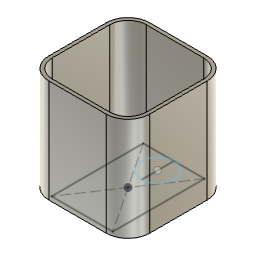
ESP32_S3_CAM_OV3660 v1 (Autodesk Fusion 360 design; units mm, degrees)
Autodesk Fusion 360 part; units mm, degrees
sketch "草图1" plane through (0, 0, 0) normal (0, 0, 1) x (1, 0, 0)
  line L0 (-12, 20) -> (12, 20)
  line L1 (20, 12) -> (20, -12)
  line L2 (12, -20) -> (-12, -20)
  line L3 (-20, -12) -> (-20, 12)
  line L4 (-20, 20) -> (20, -20) construction
  line L5 (20, 20) -> (-20, -20) construction
  arc A0 (-12, 20) -> (-20, 12) centre (-12, 12) ccw
  arc A1 (20, 12) -> (12, 20) centre (12, 12) ccw
  arc A2 (-20, -12) -> (-12, -20) centre (-12, -12) ccw
  arc A3 (12, -20) -> (20, -12) centre (12, -12) ccw
  arc A4 (12, -18.5) -> (18.5, -12) centre (12, -12) ccw
  line L6 (18.5, 12) -> (18.5, -12)
  arc A5 (18.5, 12) -> (12, 18.5) centre (12, 12) ccw
  line L7 (-12, 18.5) -> (12, 18.5)
  arc A6 (-12, 18.5) -> (-18.5, 12) centre (-12, 12) ccw
  line L8 (-18.5, -12) -> (-18.5, 12)
  arc A7 (-18.5, -12) -> (-12, -18.5) centre (-12, -12) ccw
  line L9 (12, -18.5) -> (-12, -18.5)
  line L10 (-10, 20) -> (10, 20)
  line L11 (10, 20) -> (10, -20)
  line L12 (10, -20) -> (-10, -20)
  line L13 (-10, -20) -> (-10, 20)
  line L14 (-10, 20) -> (10, -20) construction
  line L15 (10, 20) -> (-10, -20) construction
  line L16 (20, 0) -> (2.5, 0)
  line L17 (0, 2.5) -> (0, 20)
  arc A8 (-18.1617, -17.1022) -> (-17.1022, -18.1617) centre (-17.6569, -17.6569) ccw
  arc A9 (-17.1022, 18.1617) -> (-18.1617, 17.1022) centre (-17.6569, 17.6569) ccw
  arc A10 (18.1617, 17.1022) -> (17.1022, 18.1617) centre (17.6569, 17.6569) ccw
  arc A11 (17.1022, -18.1617) -> (18.1617, -17.1022) centre (17.6569, -17.6569) ccw
  dimension "d1" = 40
  dimension "d2" = 40
  dimension "d3" = 8
  dimension "d4" = 1.5
  dimension "d29" = 20
  dimension "d30" = 40
  dimension "d63" = 1.5
  constraint horizontal L0
  constraint perpendicular L0 L1
  constraint parallel L0 L2
  constraint parallel L1 L3
  constraint coincident L4 origin
  constraint coincident L5 origin
  constraint coincident L4.start L3
  constraint coincident L4.start L0
  constraint tangent L3 A0
  constraint tangent L0 A0
  constraint coincident L5.start L0
  constraint coincident L5.start L1
  constraint tangent L0 A1
  constraint tangent L1 A1
  constraint equal A0 A1
  constraint coincident L5.end L3
  constraint coincident L5.end L2
  constraint tangent L3 A2
  constraint tangent L2 A2
  constraint equal A0 A2
  constraint coincident L4.end L2
  constraint coincident L4.end L1
  constraint tangent L2 A3
  constraint tangent L1 A3
  constraint equal A0 A3
  constraint horizontal L10
  constraint perpendicular L10 L11
  constraint parallel L10 L12
  constraint parallel L11 L13
  constraint coincident L14 origin
  constraint coincident L15 origin
  constraint midpoint A2 A8.centre
  constraint coincident A2 A8.end
  constraint coincident A2 A8.start
  constraint symmetric L16 A8.end A9.start
  constraint symmetric L16 A8 A9
  constraint symmetric L16 A8.start A9.end
  constraint symmetric L17 A8.end A11.start
  constraint symmetric L17 A8 A11
  constraint symmetric L17 A8.start A11.end
  constraint symmetric L17 A9.end A10.start
  constraint symmetric L17 A9.start A10.end
  constraint symmetric L17 A9 A10
  measures "d1" distance of L4.end L5.end
  measures "d2" distance of L5.start L4.end
  measures "d3" radius of A0
  measures "d29" distance of L11.end L12.end
  measures "d30" distance of L10.end L11.end
  measures "d63" diameter of A8
ref_plane "工作平面1" through (0, 0, 1.5) normal (0, 0, 1) x (1, 0, 0)
sketch "草图3" plane through (0, 0, 1.5) normal (0, 0, 1) x (1, 0, 0)
  line L0 (15, 17) -> (15, -17)
  line L1 (-15, -17) -> (-15, 17)
  line L2 (-15, 23) -> (15, -23) construction
  line L3 (15, 23) -> (-15, -23) construction
  line L4 (13.5, -20.7) -> (13.5, -21.5)
  line L5 (13.5, 17) -> (13.5, -17)
  line L6 (-13.5, -17) -> (-13.5, 17)
  line L7 (-13.5, 20.7) -> (-13.5, 21.5)
  line L8 (15, -17) -> (13.5, -17)
  line L9 (-13.5, -17) -> (-15, -17)
  line L10 (15, 17) -> (13.5, 17)
  line L11 (-13.5, 17) -> (-15, 17)
  dimension "d10" = 30
  constraint parallel L0 L1
  constraint coincident L2 origin
  constraint coincident L3 origin
  constraint perpendicular L1 L10
  constraint perpendicular L1 L8
  constraint coincident L2 L4.start
  constraint coincident L6.start L8
  constraint coincident L6.end L10
  constraint coincident L2 L7.start
  constraint collinear L6 L7
  constraint collinear L8 L9
  constraint collinear L10 L11
  measures "d10" distance of L2.end L3.end
sketch "草图5" plane through (0, 0, 0) normal (0, 1, 0) x (1, 0, 0)
  line L0 (13.5, -40) -> (13.5, -1.5)
  line L1 (-13.5, -1.5) -> (-13.5, -40)
  line L2 (13.5, -40) -> (13.5, -1.5)
  line L3 (13.5, -1.5) -> (-13.5, -1.5)
  line L4 (-13.5, -1.5) -> (-13.5, -40)
  line L5 (13.5, -50) -> (-13.5, -50)
  line L6 (-13.5, -50) -> (-13.5, -1.5)
  line L7 (-13.5, 50) -> (13.5, 50)
  line L8 (13.5, -1.5) -> (13.5, -50)
  dimension "d18" = 38.5
  dimension "d19" = 100
  constraint parallel L0 L1
  constraint vertical L2
  constraint horizontal L3
  constraint vertical L4
  constraint horizontal L5
  constraint perpendicular L5 L6
  constraint parallel L5 L7
  constraint parallel L6 L8
  measures "d18" distance of L1.end L1.start
  measures "d19" distance of L5.end L7.start
sketch "草图6" plane through (0, 0, 0) normal (1, 0, 0) x (0, 1, 0)
  line L0 (-10, 50) -> (10, 50)
  line L1 (10, 50) -> (10, 1.5)
  line L2 (-10, 1.5) -> (-10, 50)
  line L3 (-0.3, 1.5) -> (0, 0) construction
  line L4 (0.3, 1.5) -> (0, 0) construction
  line L5 (-10, 50) -> (10, 50)
  line L6 (10, 50) -> (10, 1.5)
  line L7 (10, 1.5) -> (-10, 1.5)
  line L8 (-10, 1.5) -> (-10, 50)
  dimension "d26" = 48.5
  constraint horizontal L0
  constraint perpendicular L0 L1
  constraint parallel L1 L2
  constraint coincident L3 L4.end
  constraint coincident L4 L3.end
  constraint coincident L3.end L4.end
  constraint horizontal L5
  constraint vertical L6
  constraint horizontal L7
  constraint vertical L8
  constraint coincident L7 L3.start
  constraint coincident L7 L4.start
  measures "d26" distance of L0.start L2.start
sketch "草图7" plane through (0, 0, 1.5) normal (0, 0, 1) x (1, 0, 0)
sketch "草图8" plane through (0, 0, 0) normal (0, 0, 1) x (1, 0, 0)
  line L0 (7, -5) -> (-7, -5) construction
  line L1 (-7, -5) -> (-7, -19) construction
  line L2 (-7, -5) -> (7, -5) construction
  line L3 (7, -5) -> (7, -19) construction
  line L4 (1.6852, -19) -> (-1.6852, -19) construction
  line L5 (-7, -5) -> (7, -19) construction
  line L6 (7, -5) -> (-7, -19) construction
  circle A0 centre (0, -12) radius 7.2
  line L7 (-9, -3) -> (-9, -19)
  line L8 (9, -19) -> (9, -3)
  line L9 (9, -3) -> (-9, -21) construction
  line L10 (-9, -3) -> (9, -21) construction
  line L11 (-10.5, -3) -> (-10.5, -19)
  line L12 (10.5, -19) -> (10.5, -3)
  line L13 (9, -3) -> (10.5, -3)
  line L14 (-9, -3) -> (-10.5, -3)
  line L15 (9, -19) -> (10.5, -19)
  line L16 (-9, -19) -> (-10.5, -19)
  line L17 (10.5, -19) -> (9, -19)
  point P0 (0, -12)
  dimension "d44" = 14.4
  dimension "d59" = 1.5
  dimension "d60" = 1.5
  constraint horizontal L0
  constraint vertical L1
  constraint horizontal L2
  constraint vertical L3
  constraint horizontal L4
  constraint midpoint L6 P0
  constraint parallel L7 L8
  constraint coincident L9 P0
  constraint coincident L10 P0
  constraint coincident P0 A0.centre
  constraint perpendicular L12 L13
  constraint perpendicular L7 L14
  constraint perpendicular L3 L15
  constraint perpendicular L11 L16
  constraint coincident A0 L4.start
  constraint coincident A0 L4.end
  measures "d44" diameter of A0
  measures "d59" distance of L8.end L12.end
  measures "d60" distance of L7.start L11.start
extrude "拉伸17" add sketch "草图1" along normal blind 43.5 contours L0 L2 L3 A0 A2 L7 A6 L8 A7 L9 L13 | L0 L7 L10 L13 L17 | L0 L7 L10 L11 L17 | L0 L1 A1 L6 A5 L7 L11 L16 | L2 L9 L11 L12 L13 | L1 L2 A3 A4 L6 L9 L11 L16 makes body 1
extrude "拉伸18" add sketch "草图1" along normal blind 1.5 separate body contours L7 A6 L8 A7 L9 L13 | L7 L9 L11 L13 | L6 A5 L7 L11 L16 | A4 L6 L9 L11 L16 makes body 2
extrude "拉伸19" cut sketch "草图5" along normal mid plane 82 bodies 1
extrude "拉伸20" cut sketch "草图6" along normal mid plane 84 bodies 1
extrude "拉伸21" cut sketch "草图8" along normal blind 16 contours A0 bodies 1 2
extrude "拉伸22" add sketch "草图8" along normal blind 17 separate body contours L7 L11 L14 L16 | L8 L12 L13 L15 L17 makes body 3 at (9, -13.6667, 5.6667) makes body 4 at (-9, -8.3333, 5.6667)
extrude "拉伸23" add sketch "草图1" along normal blind 17 separate body contours L0 L7 L10 L13 L17 | L0 L7 L10 L11 L17 makes body 5
extrude "拉伸25" add sketch "草图3" along normal blind 16.5 separate body makes body 6 at (15, 5.6667, 12.5) makes body 7 at (-15, -5.6667, 12.5)
extrude "拉伸26" add sketch "草图1" along normal blind 43.5 separate body contours A0 A9 | A1 A10 | A2 A8 | A3 A11 makes body 8 at (17.875, -18.3744, 29) makes body 9 at (18.1606, 18.2125, 29) makes body 10 at (-18.1606, -18.2125, 29) makes body 11 at (-18.0426, 18.3, 29)
extrude "拉伸27" cut sketch "草图1" along normal blind 1 contours A0 A9 | A1 A10 | A2 A8 | A3 A11 bodies 8 9 10 11
sketch "草图9" plane through (0, 0, 0) normal (0, 0, 1) x (1, 0, 0)
  line L0 (-12.5, 20.5) -> (12.5, 20.5)
  line L1 (20.5, 12.5) -> (20.5, -12.5)
  line L2 (12.5, -20.5) -> (-12.5, -20.5)
  line L3 (-20.5, -12.5) -> (-20.5, 12.5)
  line L4 (-20.5, 20.5) -> (20.5, -20.5) construction
  line L5 (20.5, 20.5) -> (-20.5, -20.5) construction
  arc A0 (-12.5, 20.5) -> (-20.5, 12.5) centre (-12.5, 12.5) ccw
  arc A1 (20.5, 12.5) -> (12.5, 20.5) centre (12.5, 12.5) ccw
  arc A2 (12.5, -20.5) -> (20.5, -12.5) centre (12.5, -12.5) ccw
  arc A3 (-20.5, -12.5) -> (-12.5, -20.5) centre (-12.5, -12.5) ccw
  arc A4 (12.5, -22) -> (22, -12.5) centre (12.5, -12.5) ccw
  line L6 (22, 12.5) -> (22, -12.5)
  arc A5 (22, 12.5) -> (12.5, 22) centre (12.5, 12.5) ccw
  line L7 (-12.5, 22) -> (12.5, 22)
  arc A6 (-12.5, 22) -> (-22, 12.5) centre (-12.5, 12.5) ccw
  line L8 (-22, -12.5) -> (-22, 12.5)
  arc A7 (-22, -12.5) -> (-12.5, -22) centre (-12.5, -12.5) ccw
  line L9 (12.5, -22) -> (-12.5, -22)
  dimension "d86" = 41
  dimension "d87" = 41
  dimension "d88" = 8
  dimension "d89" = 8
  dimension "d90" = 8
  dimension "d91" = 8
  dimension "d92" = -1.5
  constraint horizontal L0
  constraint perpendicular L0 L1
  constraint parallel L0 L2
  constraint parallel L1 L3
  constraint coincident L4 origin
  constraint coincident L5 origin
  constraint coincident L4.start L3
  constraint coincident L4.start L0
  constraint tangent L3 A0
  constraint tangent L0 A0
  constraint coincident L5.start L1
  constraint coincident L5.start L0
  constraint tangent L1 A1
  constraint tangent L0 A1
  constraint coincident L4.end L1
  constraint coincident L4.end L2
  constraint tangent L1 A2
  constraint tangent L2 A2
  constraint coincident L5.end L2
  constraint coincident L5.end L3
  constraint tangent L2 A3
  constraint tangent L3 A3
  measures "d86" distance of L4.end L5.end
  measures "d87" distance of L5.start L4.end
  measures "d88" radius of A0
  measures "d89" radius of A1
  measures "d90" radius of A2
  measures "d91" radius of A3
extrude "拉伸28" add sketch "草图9" along normal blind 1.5 separate body contours L0 L1 L2 L3 A0 A1 A2 A3 makes body 12
extrude "拉伸29" add sketch "草图9" along normal blind 45 bodies 12
ref_plane "工作平面2" through (-15, 17, 18) normal (0, 0, -1) x (-1, 0, 0)
sketch "草图10" plane through (0, 0, 18) normal (0, 0, -1) x (-1, 0, 0)
  line L0 (15, 8) -> (12.5, 8)
  line L1 (12.5, 8) -> (12.5, 4)
  line L2 (12.5, 4) -> (15, 4)
  line L3 (15, 4) -> (15, 8)
  line L4 (0, 2.5) -> (0, 20)
  line L5 (-15, 8) -> (-12.5, 8)
  line L6 (-15, 4) -> (-15, 8)
  line L7 (-12.5, 8) -> (-12.5, 4)
  line L8 (-12.5, 4) -> (-15, 4)
  dimension "d107" = 2.5
  dimension "d108" = 4
  constraint horizontal L0
  constraint vertical L1
  constraint horizontal L2
  constraint vertical L3
  constraint symmetric L0.start L4 L5.start
  constraint symmetric L0.end L4 L5.end
  constraint symmetric L1.end L4 L7.end
  constraint symmetric L2.end L4 L6.start
  measures "d107" distance of L0.start L0.end
  measures "d108" distance of L0.start L2.end
extrude "拉伸30" add sketch "草图10" against normal blind 2 bodies 6 7
fillet "圆角1" radius 2.5 1 edges at (-12.5, 6, 20) on bodies 7
fillet "圆角2" radius 2.5 1 edges at (12.5, 6, 20) on bodies 6
combine "合并1" operation add target body 1 tool bodies 2 4 3 6 5 11 8 9 7 10 keep tools result as body 13 in component "Component"
sketch "草图11" plane through (0, 0, 0) normal (0, 0, 1) x (1, 0, 0)
  line L0 (-11.25, 6.25) -> (11.25, 6.25)
  line L1 (11.25, 6.25) -> (11.25, -6.25)
  line L2 (11.25, -6.25) -> (-11.25, -6.25)
  line L3 (-11.25, -6.25) -> (-11.25, 6.25)
  line L4 (-11.25, 6.25) -> (11.25, -6.25) construction
  line L5 (11.25, 6.25) -> (-11.25, -6.25) construction
  dimension "d115" = 22.5
  dimension "d116" = 12.5
  constraint horizontal L0
  constraint perpendicular L0 L1
  constraint parallel L0 L2
  constraint parallel L1 L3
  constraint coincident L4 origin
  constraint coincident L5 origin
  measures "d115" distance of L1.end L2.end
  measures "d116" distance of L0.end L1.end
extrude "拉伸31" add sketch "草图11" along normal blind 19.3 separate body makes body 14
ref_plane "工作平面3" through (0, 0, 19.3) normal (0, 0, 1) x (1, 0, 0)
sketch "草图12" plane through (0, 0, 19.3) normal (0, 0, 1) x (1, 0, 0)
  line L0 (16.1, -6.25) -> (-16.1, -6.25)
  line L1 (-16.1, -6.25) -> (-16.1, 6.25)
  line L2 (-16.1, 6.25) -> (16.1, 6.25)
  line L3 (16.1, 6.25) -> (16.1, -6.25)
  line L4 (16.1, -6.25) -> (-16.1, 6.25) construction
  line L5 (-16.1, -6.25) -> (16.1, 6.25) construction
  line L6 (-16.1, 0) -> (-14.1, 0)
  line L7 (16.1, 0) -> (14.1, 0)
  circle A0 centre (-14.1, 0) radius 1
  line L8 (0, 2.5) -> (0, 20)
  circle A1 centre (14.1, 0) radius 1
  dimension "d120" = 32.2
  dimension "d121" = 12.5
  dimension "d126" = 2
  dimension "d127" = 2
  dimension "d128" = 2
  constraint horizontal L0
  constraint perpendicular L0 L1
  constraint parallel L0 L2
  constraint parallel L1 L3
  constraint coincident L4 origin
  constraint coincident L5 origin
  constraint midpoint L1 L6.start
  constraint perpendicular L1 L6
  constraint midpoint L3 L7.start
  constraint perpendicular L3 L7
  constraint coincident L6.end A0.centre
  constraint symmetric A0 L8 A1
  measures "d120" distance of L1.end L2.end
  measures "d121" distance of L0.end L1.end
  measures "d126" distance of L6.start L6.end
  measures "d127" distance of L7.start L7.end
  measures "d128" diameter of A0
extrude "拉伸32" add sketch "草图12" against normal blind 2.5 contours L0 L1 L2 L3 | A0 | A1 bodies 14
extrude "拉伸33" add sketch "草图11" along normal blind 23.2 separate body makes body 15
extrude "拉伸34" cut sketch "草图12" against normal blind 4 contours A0 | A1 bodies 14
ref_plane "工作平面4" through (0, 0, 23.2) normal (0, 0, 1) x (1, 0, 0)
sketch "草图13" plane through (0, 0, 23.2) normal (0, 0, 1) x (1, 0, 0)
  line L0 (-11.25, -6.25) -> (-11.25, 6.25)
  line L1 (11.25, 6.25) -> (-11.25, 6.25)
  line L2 (16.1, -6.25) -> (-16.1, -6.25)
  circle A0 centre (-5, 0) radius 6.25
  line L3 (-5, 0) -> (0.8, 0)
  circle A1 centre (0.8, 0) radius 2.8
  circle A2 centre (-5, 0) radius 2.5
  dimension "d132" = 5.8
  dimension "d133" = 5.6
  dimension "d136" = 5
  constraint tangent L0 A0
  constraint tangent L1 A0
  constraint tangent L2 A0
  constraint coincident A0.centre L3.start
  constraint horizontal L3
  constraint coincident L3.end A1.centre
  constraint concentric A0 A2
  measures "d132" distance of A0.centre L3.end
  measures "d133" diameter of A1
  measures "d136" diameter of A2
extrude "拉伸35" add sketch "草图13" along normal blind 4.5 contours A0 A1 | A0 A1 | A0 A1 | A2 bodies 15
extrude "拉伸36" add sketch "草图13" along normal blind 7.5 separate body contours A2 makes body 16
combine "合并1'" operation add target body 16 tool bodies 15 14 keep tools result as body 17 in component "9g"
move_body "移动1" bodies 13 to x (1, 0, 0) y (0, 1, 0) z (0, 0, 1) at (0, 41, 0) in component "Component"
sketch "草图14" plane through (0, 0, 0) normal (0, 0, 1) x (1, 0, 0)
  line L0 (-13.35, 20) -> (13.35, 20)
  line L1 (13.35, 20) -> (13.35, -20)
  line L2 (13.35, -20) -> (-13.35, -20)
  line L3 (-13.35, -20) -> (-13.35, 20)
  line L4 (-13.35, 20) -> (13.35, -20) construction
  line L5 (13.35, 20) -> (-13.35, -20) construction
  line L6 (0, 20) -> (0, 6)
  circle A0 centre (0, 13) radius 7
  dimension "d139" = 26.7
  dimension "d140" = 40
  dimension "d141" = 14
  constraint horizontal L0
  constraint perpendicular L0 L1
  constraint parallel L0 L2
  constraint parallel L1 L3
  constraint coincident L4 origin
  constraint coincident L5 origin
  constraint midpoint L0 L6.start
  constraint perpendicular L0 L6
  constraint coincident L6.end A0
  constraint coincident L6.start A0
  measures "d139" distance of L1.end L2.end
  measures "d140" distance of L0.end L1.end
  measures "d141" distance of L6.start L6.end
extrude "拉伸37" add sketch "草图14" against normal blind 1 separate body contours L6 A0 | L6 A0 | L0 L1 L2 L3 makes body 18
extrude "拉伸38" add sketch "草图14" along normal blind 18 contours L6 A0 | L6 A0 bodies 18
component "Component" placed x (1, 0, 0) y (0, 1, 0) z (0, 0, 1) at (0, 0, 0)
component "9g" placed x (1, 0, 0) y (0, 1, 0) z (0, 0, 1) at (0, 0, 0)
named bodies: "周围", "内挡左", "内挡右", "前挡", "外挡左", "外挡右", "柱1", "柱2", "柱3", "柱4"
